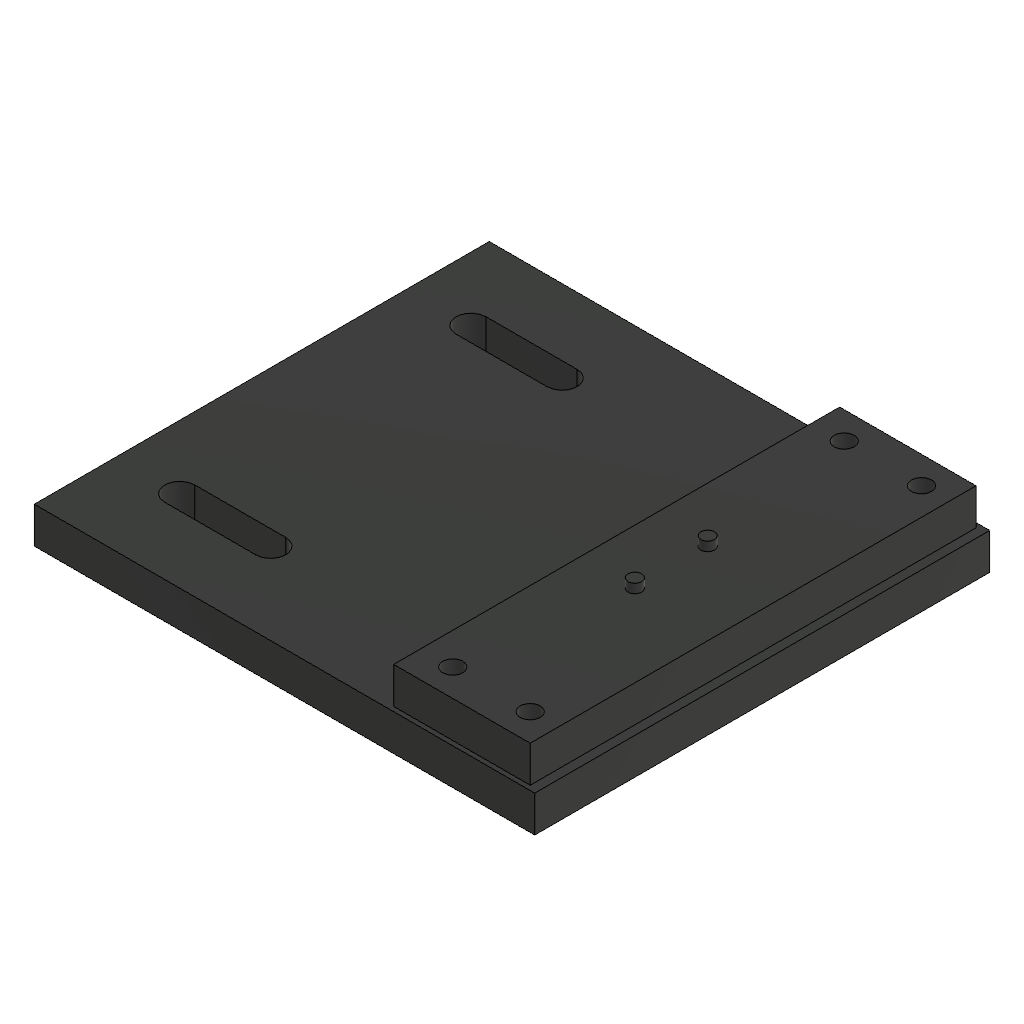
root_base (Autodesk Fusion 360 design; units mm, degrees)
part number: 2026-10-10-16-37-38-776
Autodesk Fusion 360 part; units mm, degrees
sketch "Bench mounting plate sketch" plane through (0, 0, 0) normal (0, 0, 1) x (1, 0, 0)
  line L0 (-82, -50) -> (28, -50)
  line L1 (28, -50) -> (28, 50)
  line L2 (28, 50) -> (-82, 50)
  line L3 (-82, 50) -> (-82, -50)
extrude "Bench mounting plate" add sketch "Bench mounting plate sketch" along normal blind 8
ref_plane "WorkPlane1" through (0, 0, 8) normal (0, 0, 1) x (1, 0, 0)
sketch "Lower root jaw sketch" plane through (0, 0, 8) normal (0, 0, 1) x (1, 0, 0)
  line L0 (-4, -49) -> (26, -49)
  line L1 (26, -49) -> (26, 49)
  line L2 (26, 49) -> (-4, 49)
  line L3 (-4, 49) -> (-4, -49)
extrude "Lower root jaw" add sketch "Lower root jaw sketch" along normal blind 8
ref_plane "WorkPlane2" through (0, 0, 15.95) normal (0, 0, 1) x (1, 0, 0)
sketch "Root pin -8 sketch" plane through (0, 0, 15.95) normal (0, 0, 1) x (1, 0, 0)
  circle A0 centre (8, -8) radius 1.5
extrude "Root pin -8" add sketch "Root pin -8 sketch" along normal blind 2.05
ref_plane "WorkPlane3" through (0, 0, 15.95) normal (0, 0, 1) x (1, 0, 0)
sketch "Root pin 8 sketch" plane through (0, 0, 15.95) normal (0, 0, 1) x (1, 0, 0)
  circle A0 centre (8, 8) radius 1.5
extrude "Root pin 8" add sketch "Root pin 8 sketch" along normal blind 2.05
ref_plane "WorkPlane4" through (0, 0, -0.05) normal (0, 0, 1) x (1, 0, 0)
sketch "Jaw bolt 3 -43 sketch" plane through (0, 0, -0.05) normal (0, 0, 1) x (1, 0, 0)
  circle A0 centre (3, -43) radius 2.2
  dimension "d173" = 4.4
  measures "d173" diameter of A0
extrude "Jaw bolt 3 -43" cut sketch "Jaw bolt 3 -43 sketch" along normal blind 16.1
ref_plane "WorkPlane5" through (0, 0, -0.05) normal (0, 0, 1) x (1, 0, 0)
sketch "Nut pocket 3 -43 sketch" plane through (0, 0, -0.05) normal (0, 0, 1) x (1, 0, 0)
  line L0 (6.55, -40.9504) -> (3, -38.9008)
  line L1 (3, -38.9008) -> (-0.55, -40.9504)
  line L2 (-0.55, -40.9504) -> (-0.55, -45.0496)
  line L3 (-0.55, -45.0496) -> (3, -47.0992)
  line L4 (3, -47.0992) -> (6.55, -45.0496)
  line L5 (6.55, -45.0496) -> (6.55, -40.9504)
extrude "Nut pocket 3 -43" cut sketch "Nut pocket 3 -43 sketch" along normal blind 3.35
ref_plane "WorkPlane6" through (0, 0, -0.05) normal (0, 0, 1) x (1, 0, 0)
sketch "Jaw bolt 3 43 sketch" plane through (0, 0, -0.05) normal (0, 0, 1) x (1, 0, 0)
  circle A0 centre (3, 43) radius 2.2
  dimension "d182" = 4.4
  measures "d182" diameter of A0
extrude "Jaw bolt 3 43" cut sketch "Jaw bolt 3 43 sketch" along normal blind 16.1
ref_plane "WorkPlane7" through (0, 0, -0.05) normal (0, 0, 1) x (1, 0, 0)
sketch "Nut pocket 3 43 sketch" plane through (0, 0, -0.05) normal (0, 0, 1) x (1, 0, 0)
  line L0 (6.55, 45.0496) -> (3, 47.0992)
  line L1 (3, 47.0992) -> (-0.55, 45.0496)
  line L2 (-0.55, 45.0496) -> (-0.55, 40.9504)
  line L3 (-0.55, 40.9504) -> (3, 38.9008)
  line L4 (3, 38.9008) -> (6.55, 40.9504)
  line L5 (6.55, 40.9504) -> (6.55, 45.0496)
extrude "Nut pocket 3 43" cut sketch "Nut pocket 3 43 sketch" along normal blind 3.35
ref_plane "WorkPlane8" through (0, 0, -0.05) normal (0, 0, 1) x (1, 0, 0)
sketch "Jaw bolt 20 -43 sketch" plane through (0, 0, -0.05) normal (0, 0, 1) x (1, 0, 0)
  circle A0 centre (20, -43) radius 2.2
  dimension "d191" = 4.4
  measures "d191" diameter of A0
extrude "Jaw bolt 20 -43" cut sketch "Jaw bolt 20 -43 sketch" along normal blind 16.1
ref_plane "WorkPlane9" through (0, 0, -0.05) normal (0, 0, 1) x (1, 0, 0)
sketch "Nut pocket 20 -43 sketch" plane through (0, 0, -0.05) normal (0, 0, 1) x (1, 0, 0)
  line L0 (23.55, -40.9504) -> (20, -38.9008)
  line L1 (20, -38.9008) -> (16.45, -40.9504)
  line L2 (16.45, -40.9504) -> (16.45, -45.0496)
  line L3 (16.45, -45.0496) -> (20, -47.0992)
  line L4 (20, -47.0992) -> (23.55, -45.0496)
  line L5 (23.55, -45.0496) -> (23.55, -40.9504)
extrude "Nut pocket 20 -43" cut sketch "Nut pocket 20 -43 sketch" along normal blind 3.35
ref_plane "WorkPlane10" through (0, 0, -0.05) normal (0, 0, 1) x (1, 0, 0)
sketch "Jaw bolt 20 43 sketch" plane through (0, 0, -0.05) normal (0, 0, 1) x (1, 0, 0)
  circle A0 centre (20, 43) radius 2.2
  dimension "d200" = 4.4
  measures "d200" diameter of A0
extrude "Jaw bolt 20 43" cut sketch "Jaw bolt 20 43 sketch" along normal blind 16.1
ref_plane "WorkPlane11" through (0, 0, -0.05) normal (0, 0, 1) x (1, 0, 0)
sketch "Nut pocket 20 43 sketch" plane through (0, 0, -0.05) normal (0, 0, 1) x (1, 0, 0)
  line L0 (23.55, 45.0496) -> (20, 47.0992)
  line L1 (20, 47.0992) -> (16.45, 45.0496)
  line L2 (16.45, 45.0496) -> (16.45, 40.9504)
  line L3 (16.45, 40.9504) -> (20, 38.9008)
  line L4 (20, 38.9008) -> (23.55, 40.9504)
  line L5 (23.55, 40.9504) -> (23.55, 45.0496)
extrude "Nut pocket 20 43" cut sketch "Nut pocket 20 43 sketch" along normal blind 3.35
ref_plane "WorkPlane12" through (0, 0, -0.05) normal (0, 0, 1) x (1, 0, 0)
sketch "Bench slot -32 sketch" plane through (0, 0, -0.05) normal (0, 0, 1) x (1, 0, 0)
  arc A0 (-68, -28.7) -> (-68, -35.3) centre (-68, -32) ccw
  line L0 (-68, -28.7) -> (-48, -28.7)
  arc A1 (-48, -35.3) -> (-48, -28.7) centre (-48, -32) ccw
  line L1 (-48, -35.3) -> (-68, -35.3)
extrude "Bench slot -32" cut sketch "Bench slot -32 sketch" along normal blind 8.1
ref_plane "WorkPlane13" through (0, 0, -0.05) normal (0, 0, 1) x (1, 0, 0)
sketch "Bench slot 32 sketch" plane through (0, 0, -0.05) normal (0, 0, 1) x (1, 0, 0)
  arc A0 (-68, 35.3) -> (-68, 28.7) centre (-68, 32) ccw
  line L0 (-68, 35.3) -> (-48, 35.3)
  arc A1 (-48, 28.7) -> (-48, 35.3) centre (-48, 32) ccw
  line L1 (-48, 28.7) -> (-68, 28.7)
extrude "Bench slot 32" cut sketch "Bench slot 32 sketch" along normal blind 8.1
equation "d173 = m4Clearance"
equation "d182 = m4Clearance"
equation "d191 = m4Clearance"
equation "d200 = m4Clearance"
equation "m4Clearance = 4.4 mm" comment "Root clamp bolt holes"
named bodies: "root_base - printable solid"
